Autodesk Fusion 360 part; units mm, degrees
(part 3 of 4)
extrude "GPU lower metal tab exit (1)" cut sketch "草图12 (4)" along normal blind 20.2 bodies 34 in component "18_ONE_PIECE_REAR_LOAD_BEAM_304_45mm"
ref_plane "工作平面13" through (0, -253.84, 0) normal (0, 1, 0) x (0, 0, 1) in component "18_ONE_PIECE_REAR_LOAD_BEAM_304_45mm"
sketch "草图13 (4)" plane through (0, -253.84, 0) normal (0, 1, 0) x (1, 0, 0) in component "18_ONE_PIECE_REAR_LOAD_BEAM_304_45mm"
  circle A0 through (5.7, -132, 507.68) (3.15, -130.5278, 507.68) (3.15, -133.4722, 507.68)
extrude "Rear end screw clearance" cut sketch "草图13 (4)" along normal blind 8 contours A0 in plane through (0, 253.84, 0) normal (0, 1, 0) bodies 34 in component "18_ONE_PIECE_REAR_LOAD_BEAM_304_45mm"
ref_plane "工作平面14" through (0, -256.84, 0) normal (0, 1, 0) x (0, 0, 1) in component "18_ONE_PIECE_REAR_LOAD_BEAM_304_45mm"
sketch "草图14 (4)" plane through (0, -256.84, 0) normal (0, 1, 0) x (1, 0, 0) in component "18_ONE_PIECE_REAR_LOAD_BEAM_304_45mm"
  circle A0 through (7.3, -132, 513.68) (2.35, -129.1421, 513.68) (2.35, -134.8579, 513.68)
extrude "Rear end screw head well leaving 3 mm web" cut sketch "草图14 (4)" along normal blind 5.01 contours A0 in plane through (0, 256.84, 0) normal (0, 1, 0) bodies 34 in component "18_ONE_PIECE_REAR_LOAD_BEAM_304_45mm"
ref_plane "工作平面15" through (0, -253.84, 0) normal (0, 1, 0) x (0, 0, 1) in component "18_ONE_PIECE_REAR_LOAD_BEAM_304_45mm"
sketch "草图15 (3)" plane through (0, -253.84, 0) normal (0, 1, 0) x (1, 0, 0) in component "18_ONE_PIECE_REAR_LOAD_BEAM_304_45mm"
  circle A0 through (295.7, -132, 507.68) (293.15, -130.5278, 507.68) (293.15, -133.4722, 507.68)
extrude "Rear end screw clearance (1)" cut sketch "草图15 (3)" along normal blind 8 contours A0 in plane through (0, 253.84, 0) normal (0, 1, 0) bodies 34 in component "18_ONE_PIECE_REAR_LOAD_BEAM_304_45mm"
ref_plane "工作平面16" through (0, -256.84, 0) normal (0, 1, 0) x (0, 0, 1) in component "18_ONE_PIECE_REAR_LOAD_BEAM_304_45mm"
sketch "草图16 (3)" plane through (0, -256.84, 0) normal (0, 1, 0) x (1, 0, 0) in component "18_ONE_PIECE_REAR_LOAD_BEAM_304_45mm"
  circle A0 through (297.3, -132, 513.68) (292.35, -129.1421, 513.68) (292.35, -134.8579, 513.68)
extrude "Rear end screw head well leaving 3 mm web (1)" cut sketch "草图16 (3)" along normal blind 5.01 contours A0 in plane through (0, 256.84, 0) normal (0, 1, 0) bodies 34 in component "18_ONE_PIECE_REAR_LOAD_BEAM_304_45mm"
ref_plane "工作平面1" through (0, 0, 148) normal (0, 0, 1) x (1, 0, 0) in component "20_ONE_PIECE_DUAL_140_FAN_RAIL_284mm"
sketch "草图1 (31)" plane through (0, 0, 148) normal (0, 0, 1) x (1, 0, 0) in component "20_ONE_PIECE_DUAL_140_FAN_RAIL_284mm"
  line L0 (12.4, -25) -> (296.4, -25)
  line L1 (296.4, -25) -> (296.4, -19)
  line L2 (296.4, -19) -> (12.4, -19)
  line L3 (12.4, -19) -> (12.4, -25)
extrude "One piece dual fan lower mounting rail" add sketch "草图1 (31)" along normal blind 12 separate body makes body 35 in component "20_ONE_PIECE_DUAL_140_FAN_RAIL_284mm"
ref_plane "工作平面2" through (0, 0, 140) normal (0, 0, 1) x (1, 0, 0) in component "20_ONE_PIECE_DUAL_140_FAN_RAIL_284mm"
sketch "草图2 (22)" plane through (0, 0, 140) normal (0, 0, 1) x (1, 0, 0) in component "20_ONE_PIECE_DUAL_140_FAN_RAIL_284mm"
  line L0 (45, -19) -> (55, -19)
  line L1 (55, -19) -> (55, 6)
  line L2 (55, 6) -> (45, 6)
  line L3 (45, 6) -> (45, -19)
extrude "Frame bearing arm" add sketch "草图2 (22)" along normal blind 14 bodies 35 in component "20_ONE_PIECE_DUAL_140_FAN_RAIL_284mm"
ref_plane "工作平面3" through (0, 0, 140) normal (0, 0, 1) x (1, 0, 0) in component "20_ONE_PIECE_DUAL_140_FAN_RAIL_284mm"
sketch "草图3 (21)" plane through (0, 0, 140) normal (0, 0, 1) x (1, 0, 0) in component "20_ONE_PIECE_DUAL_140_FAN_RAIL_284mm"
  circle A0 centre (50, 2) radius 1.7
extrude "Fan arm M3 clearance" cut sketch "草图3 (21)" along normal blind 14 bodies 35 in component "20_ONE_PIECE_DUAL_140_FAN_RAIL_284mm"
ref_plane "工作平面4" through (0, 0, 143) normal (0, 0, 1) x (1, 0, 0) in component "20_ONE_PIECE_DUAL_140_FAN_RAIL_284mm"
sketch "草图4 (21)" plane through (0, 0, 143) normal (0, 0, 1) x (1, 0, 0) in component "20_ONE_PIECE_DUAL_140_FAN_RAIL_284mm"
  circle A0 centre (50, 2) radius 3.3
extrude "Fan arm screw well for M3x6 leaving 3 mm web" cut sketch "草图4 (21)" along normal blind 11.01 bodies 35 in component "20_ONE_PIECE_DUAL_140_FAN_RAIL_284mm"
ref_plane "工作平面5" through (0, 0, 140) normal (0, 0, 1) x (1, 0, 0) in component "20_ONE_PIECE_DUAL_140_FAN_RAIL_284mm"
sketch "草图5 (20)" plane through (0, 0, 140) normal (0, 0, 1) x (1, 0, 0) in component "20_ONE_PIECE_DUAL_140_FAN_RAIL_284mm"
  line L0 (105, -19) -> (115, -19)
  line L1 (115, -19) -> (115, 6)
  line L2 (115, 6) -> (105, 6)
  line L3 (105, 6) -> (105, -19)
extrude "Frame bearing arm (1)" add sketch "草图5 (20)" along normal blind 14 bodies 35 in component "20_ONE_PIECE_DUAL_140_FAN_RAIL_284mm"
ref_plane "工作平面6" through (0, 0, 140) normal (0, 0, 1) x (1, 0, 0) in component "20_ONE_PIECE_DUAL_140_FAN_RAIL_284mm"
sketch "草图6 (18)" plane through (0, 0, 140) normal (0, 0, 1) x (1, 0, 0) in component "20_ONE_PIECE_DUAL_140_FAN_RAIL_284mm"
  circle A0 centre (110, 2) radius 1.7
extrude "Fan arm M3 clearance (1)" cut sketch "草图6 (18)" along normal blind 14 bodies 35 in component "20_ONE_PIECE_DUAL_140_FAN_RAIL_284mm"
ref_plane "工作平面7" through (0, 0, 143) normal (0, 0, 1) x (1, 0, 0) in component "20_ONE_PIECE_DUAL_140_FAN_RAIL_284mm"
sketch "草图7 (15)" plane through (0, 0, 143) normal (0, 0, 1) x (1, 0, 0) in component "20_ONE_PIECE_DUAL_140_FAN_RAIL_284mm"
  circle A0 centre (110, 2) radius 3.3
extrude "Fan arm screw well for M3x6 leaving 3 mm web (1)" cut sketch "草图7 (15)" along normal blind 11.01 bodies 35 in component "20_ONE_PIECE_DUAL_140_FAN_RAIL_284mm"
ref_plane "工作平面8" through (0, 0, 140) normal (0, 0, 1) x (1, 0, 0) in component "20_ONE_PIECE_DUAL_140_FAN_RAIL_284mm"
sketch "草图8 (13)" plane through (0, 0, 140) normal (0, 0, 1) x (1, 0, 0) in component "20_ONE_PIECE_DUAL_140_FAN_RAIL_284mm"
  line L0 (195, -19) -> (205, -19)
  line L1 (205, -19) -> (205, 6)
  line L2 (205, 6) -> (195, 6)
  line L3 (195, 6) -> (195, -19)
extrude "Frame bearing arm (2)" add sketch "草图8 (13)" along normal blind 14 bodies 35 in component "20_ONE_PIECE_DUAL_140_FAN_RAIL_284mm"
ref_plane "工作平面9" through (0, 0, 140) normal (0, 0, 1) x (1, 0, 0) in component "20_ONE_PIECE_DUAL_140_FAN_RAIL_284mm"
sketch "草图9 (10)" plane through (0, 0, 140) normal (0, 0, 1) x (1, 0, 0) in component "20_ONE_PIECE_DUAL_140_FAN_RAIL_284mm"
  circle A0 centre (200, 2) radius 1.7
extrude "Fan arm M3 clearance (2)" cut sketch "草图9 (10)" along normal blind 14 bodies 35 in component "20_ONE_PIECE_DUAL_140_FAN_RAIL_284mm"
ref_plane "工作平面10" through (0, 0, 143) normal (0, 0, 1) x (1, 0, 0) in component "20_ONE_PIECE_DUAL_140_FAN_RAIL_284mm"
sketch "草图10 (6)" plane through (0, 0, 143) normal (0, 0, 1) x (1, 0, 0) in component "20_ONE_PIECE_DUAL_140_FAN_RAIL_284mm"
  circle A0 centre (200, 2) radius 3.3
extrude "Fan arm screw well for M3x6 leaving 3 mm web (2)" cut sketch "草图10 (6)" along normal blind 11.01 bodies 35 in component "20_ONE_PIECE_DUAL_140_FAN_RAIL_284mm"
ref_plane "工作平面11" through (0, 0, 140) normal (0, 0, 1) x (1, 0, 0) in component "20_ONE_PIECE_DUAL_140_FAN_RAIL_284mm"
sketch "草图11 (5)" plane through (0, 0, 140) normal (0, 0, 1) x (1, 0, 0) in component "20_ONE_PIECE_DUAL_140_FAN_RAIL_284mm"
  line L0 (260, -19) -> (270, -19)
  line L1 (270, -19) -> (270, 6)
  line L2 (270, 6) -> (260, 6)
  line L3 (260, 6) -> (260, -19)
extrude "Frame bearing arm (3)" add sketch "草图11 (5)" along normal blind 14 bodies 35 in component "20_ONE_PIECE_DUAL_140_FAN_RAIL_284mm"
ref_plane "工作平面12" through (0, 0, 140) normal (0, 0, 1) x (1, 0, 0) in component "20_ONE_PIECE_DUAL_140_FAN_RAIL_284mm"
sketch "草图12 (5)" plane through (0, 0, 140) normal (0, 0, 1) x (1, 0, 0) in component "20_ONE_PIECE_DUAL_140_FAN_RAIL_284mm"
  circle A0 centre (265, 2) radius 1.7
extrude "Fan arm M3 clearance (3)" cut sketch "草图12 (5)" along normal blind 14 bodies 35 in component "20_ONE_PIECE_DUAL_140_FAN_RAIL_284mm"
ref_plane "工作平面13" through (0, 0, 143) normal (0, 0, 1) x (1, 0, 0) in component "20_ONE_PIECE_DUAL_140_FAN_RAIL_284mm"
sketch "草图13 (5)" plane through (0, 0, 143) normal (0, 0, 1) x (1, 0, 0) in component "20_ONE_PIECE_DUAL_140_FAN_RAIL_284mm"
  circle A0 centre (265, 2) radius 3.3
extrude "Fan arm screw well for M3x6 leaving 3 mm web (3)" cut sketch "草图13 (5)" along normal blind 11.01 bodies 35 in component "20_ONE_PIECE_DUAL_140_FAN_RAIL_284mm"
ref_plane "工作平面10" through (0, 0, 143) normal (0, 0, 1) x (1, 0, 0) in component "19_PCI_LONGITUDINAL_BOARD_RAIL_243_84mm"
sketch "草图10 (7)" plane through (0, 0, 143) normal (0, 0, 1) x (1, 0, 0) in component "19_PCI_LONGITUDINAL_BOARD_RAIL_243_84mm"
  circle A0 centre (4, 20) radius 3.3
extrude "M3x6 rail mounting head well" cut sketch "草图10 (7)" along normal blind 5.01 bodies 31 in component "19_PCI_LONGITUDINAL_BOARD_RAIL_243_84mm"
ref_plane "工作平面11" through (0, 0, 143) normal (0, 0, 1) x (1, 0, 0) in component "19_PCI_LONGITUDINAL_BOARD_RAIL_243_84mm"
sketch "草图11 (6)" plane through (0, 0, 143) normal (0, 0, 1) x (1, 0, 0) in component "19_PCI_LONGITUDINAL_BOARD_RAIL_243_84mm"
  circle A0 centre (4, 225) radius 3.3
extrude "M3x6 rail mounting head well (1)" cut sketch "草图11 (6)" along normal blind 5.01 bodies 31 in component "19_PCI_LONGITUDINAL_BOARD_RAIL_243_84mm"
ref_plane "工作平面10" through (0, 0, 143) normal (0, 0, 1) x (1, 0, 0) in component "19_CPU_LONGITUDINAL_BOARD_RAIL_243_84mm"
sketch "草图10 (8)" plane through (0, 0, 143) normal (0, 0, 1) x (1, 0, 0) in component "19_CPU_LONGITUDINAL_BOARD_RAIL_243_84mm"
  circle A0 centre (294, 20) radius 3.3
extrude "M3x6 rail mounting head well'" cut sketch "草图10 (8)" along normal blind 5.01 bodies 33 in component "19_CPU_LONGITUDINAL_BOARD_RAIL_243_84mm"
ref_plane "工作平面11" through (0, 0, 143) normal (0, 0, 1) x (1, 0, 0) in component "19_CPU_LONGITUDINAL_BOARD_RAIL_243_84mm"
sketch "草图11 (7)" plane through (0, 0, 143) normal (0, 0, 1) x (1, 0, 0) in component "19_CPU_LONGITUDINAL_BOARD_RAIL_243_84mm"
  circle A0 centre (294, 225) radius 3.3
extrude "M3x6 rail mounting head well (1)'" cut sketch "草图11 (7)" along normal blind 5.01 bodies 33 in component "19_CPU_LONGITUDINAL_BOARD_RAIL_243_84mm"
ref_plane "工作平面15" through (0, 0, 143) normal (0, 0, 1) x (1, 0, 0) in component "19_MID_LONGITUDINAL_BOARD_RAIL_243_84mm"
sketch "草图15 (4)" plane through (0, 0, 143) normal (0, 0, 1) x (1, 0, 0) in component "19_MID_LONGITUDINAL_BOARD_RAIL_243_84mm"
  circle A0 centre (134, 3) radius 3.3
extrude "M3x6 rail mounting head well''" cut sketch "草图15 (4)" along normal blind 5.01 bodies 32 in component "19_MID_LONGITUDINAL_BOARD_RAIL_243_84mm"
ref_plane "工作平面16" through (0, 0, 143) normal (0, 0, 1) x (1, 0, 0) in component "19_MID_LONGITUDINAL_BOARD_RAIL_243_84mm"
sketch "草图16 (4)" plane through (0, 0, 143) normal (0, 0, 1) x (1, 0, 0) in component "19_MID_LONGITUDINAL_BOARD_RAIL_243_84mm"
  circle A0 centre (134, 222.5) radius 3.3
extrude "M3x6 rail mounting head well (1)''" cut sketch "草图16 (4)" along normal blind 5.01 bodies 32 in component "19_MID_LONGITUDINAL_BOARD_RAIL_243_84mm"
ref_plane "工作平面23" through (0, 0, 143) normal (0, 0, 1) x (1, 0, 0) in component "07_GPU_REINFORCED_REAR_TOWER"
sketch "草图23" plane through (0, 0, 143) normal (0, 0, 1) x (1, 0, 0) in component "07_GPU_REINFORCED_REAR_TOWER"
  circle A0 centre (80, 248.5) radius 3.3
extrude "M3x6 tower base screw head well" cut sketch "草图23" along normal blind 5.01 bodies 26 in component "07_GPU_REINFORCED_REAR_TOWER"
ref_plane "工作平面24" through (0, 0, 143) normal (0, 0, 1) x (1, 0, 0) in component "07_GPU_REINFORCED_REAR_TOWER"
sketch "草图24" plane through (0, 0, 143) normal (0, 0, 1) x (1, 0, 0) in component "07_GPU_REINFORCED_REAR_TOWER"
  circle A0 centre (140, 248.5) radius 3.3
extrude "M3x6 tower base screw head well (1)" cut sketch "草图24" along normal blind 5.01 bodies 26 in component "07_GPU_REINFORCED_REAR_TOWER"
ref_plane "工作平面25" through (0, 0, 143) normal (0, 0, 1) x (1, 0, 0) in component "07_GPU_REINFORCED_REAR_TOWER"
sketch "草图25" plane through (0, 0, 143) normal (0, 0, 1) x (1, 0, 0) in component "07_GPU_REINFORCED_REAR_TOWER"
  circle A0 centre (158, 248.5) radius 3.3
extrude "M3x6 tower base screw head well (2)" cut sketch "草图25" along normal blind 5.01 bodies 26 in component "07_GPU_REINFORCED_REAR_TOWER"
ref_plane "工作平面26" through (0, -263, 0) normal (0, 1, 0) x (0, 0, 1) in component "07_GPU_REINFORCED_REAR_TOWER"
sketch "草图26" plane through (0, -263, 0) normal (0, 1, 0) x (1, 0, 0) in component "07_GPU_REINFORCED_REAR_TOWER"
  circle A0 through (83.3, -262, 526) (78.35, -259.1421, 526) (78.35, -264.8579, 526)
extrude "Upper sliding screw head channel end A" cut sketch "草图26" along normal blind 7.01 contours A0 in plane through (0, 263, 0) normal (0, 1, 0) bodies 26 in component "07_GPU_REINFORCED_REAR_TOWER"
ref_plane "工作平面27" through (0, -263, 0) normal (0, 1, 0) x (0, 0, 1) in component "07_GPU_REINFORCED_REAR_TOWER"
sketch "草图27" plane through (0, -263, 0) normal (0, 1, 0) x (1, 0, 0) in component "07_GPU_REINFORCED_REAR_TOWER"
  circle A0 through (83.3, -292, 526) (78.35, -289.1421, 526) (78.35, -294.8579, 526)
extrude "Upper sliding screw head channel end B" cut sketch "草图27" along normal blind 7.01 contours A0 in plane through (0, 263, 0) normal (0, 1, 0) bodies 26 in component "07_GPU_REINFORCED_REAR_TOWER"
ref_plane "工作平面28" through (0, 0, 262) normal (0, 0, 1) x (1, 0, 0) in component "07_GPU_REINFORCED_REAR_TOWER"
sketch "草图28" plane through (0, 0, 262) normal (0, 0, 1) x (1, 0, 0) in component "07_GPU_REINFORCED_REAR_TOWER"
  line L0 (76.7, 263) -> (83.3, 263)
  line L1 (83.3, 263) -> (83.3, 270.01)
  line L2 (83.3, 270.01) -> (76.7, 270.01)
  line L3 (76.7, 270.01) -> (76.7, 263)
extrude "Upper sliding screw head channel middle" cut sketch "草图28" along normal blind 30 bodies 26 in component "07_GPU_REINFORCED_REAR_TOWER"
ref_plane "工作平面29" through (0, -263, 0) normal (0, 1, 0) x (0, 0, 1) in component "07_GPU_REINFORCED_REAR_TOWER"
sketch "草图29" plane through (0, -263, 0) normal (0, 1, 0) x (1, 0, 0) in component "07_GPU_REINFORCED_REAR_TOWER"
  circle A0 through (83.3, -157, 526) (78.35, -154.1421, 526) (78.35, -159.8579, 526)
extrude "Lower sliding screw head channel end A" cut sketch "草图29" along normal blind 7.01 contours A0 in plane through (0, 263, 0) normal (0, 1, 0) bodies 26 in component "07_GPU_REINFORCED_REAR_TOWER"
ref_plane "工作平面30" through (0, -263, 0) normal (0, 1, 0) x (0, 0, 1) in component "07_GPU_REINFORCED_REAR_TOWER"
sketch "草图30" plane through (0, -263, 0) normal (0, 1, 0) x (1, 0, 0) in component "07_GPU_REINFORCED_REAR_TOWER"
  circle A0 through (83.3, -165, 526) (78.35, -162.1421, 526) (78.35, -167.8579, 526)
extrude "Lower sliding screw head channel end B" cut sketch "草图30" along normal blind 7.01 contours A0 in plane through (0, 263, 0) normal (0, 1, 0) bodies 26 in component "07_GPU_REINFORCED_REAR_TOWER"
ref_plane "工作平面31" through (0, 0, 157) normal (0, 0, 1) x (1, 0, 0) in component "07_GPU_REINFORCED_REAR_TOWER"
sketch "草图31" plane through (0, 0, 157) normal (0, 0, 1) x (1, 0, 0) in component "07_GPU_REINFORCED_REAR_TOWER"
  line L0 (76.7, 263) -> (83.3, 263)
  line L1 (83.3, 263) -> (83.3, 270.01)
  line L2 (83.3, 270.01) -> (76.7, 270.01)
  line L3 (76.7, 270.01) -> (76.7, 263)
extrude "Lower sliding screw head channel middle" cut sketch "草图31" along normal blind 8 bodies 26 in component "07_GPU_REINFORCED_REAR_TOWER"
ref_plane "工作平面32" through (0, -263, 0) normal (0, 1, 0) x (0, 0, 1) in component "07_GPU_REINFORCED_REAR_TOWER"
sketch "草图32" plane through (0, -263, 0) normal (0, 1, 0) x (1, 0, 0) in component "07_GPU_REINFORCED_REAR_TOWER"
  circle A0 through (167.3, -262, 526) (162.35, -259.1421, 526) (162.35, -264.8579, 526)
extrude "Upper sliding screw head channel end A (1)" cut sketch "草图32" along normal blind 7.01 contours A0 in plane through (0, 263, 0) normal (0, 1, 0) bodies 26 in component "07_GPU_REINFORCED_REAR_TOWER"
ref_plane "工作平面33" through (0, -263, 0) normal (0, 1, 0) x (0, 0, 1) in component "07_GPU_REINFORCED_REAR_TOWER"
sketch "草图33" plane through (0, -263, 0) normal (0, 1, 0) x (1, 0, 0) in component "07_GPU_REINFORCED_REAR_TOWER"
  circle A0 through (167.3, -292, 526) (162.35, -289.1421, 526) (162.35, -294.8579, 526)
extrude "Upper sliding screw head channel end B (1)" cut sketch "草图33" along normal blind 7.01 contours A0 in plane through (0, 263, 0) normal (0, 1, 0) bodies 26 in component "07_GPU_REINFORCED_REAR_TOWER"
ref_plane "工作平面34" through (0, 0, 262) normal (0, 0, 1) x (1, 0, 0) in component "07_GPU_REINFORCED_REAR_TOWER"
sketch "草图34" plane through (0, 0, 262) normal (0, 0, 1) x (1, 0, 0) in component "07_GPU_REINFORCED_REAR_TOWER"
  line L0 (160.7, 263) -> (167.3, 263)
  line L1 (167.3, 263) -> (167.3, 270.01)
  line L2 (167.3, 270.01) -> (160.7, 270.01)
  line L3 (160.7, 270.01) -> (160.7, 263)
extrude "Upper sliding screw head channel middle (1)" cut sketch "草图34" along normal blind 30 bodies 26 in component "07_GPU_REINFORCED_REAR_TOWER"
ref_plane "工作平面35" through (0, -263, 0) normal (0, 1, 0) x (0, 0, 1) in component "07_GPU_REINFORCED_REAR_TOWER"
sketch "草图35" plane through (0, -263, 0) normal (0, 1, 0) x (1, 0, 0) in component "07_GPU_REINFORCED_REAR_TOWER"
  circle A0 through (167.3, -157, 526) (162.35, -154.1421, 526) (162.35, -159.8579, 526)
extrude "Lower sliding screw head channel end A (1)" cut sketch "草图35" along normal blind 7.01 contours A0 in plane through (0, 263, 0) normal (0, 1, 0) bodies 26 in component "07_GPU_REINFORCED_REAR_TOWER"
ref_plane "工作平面36" through (0, -263, 0) normal (0, 1, 0) x (0, 0, 1) in component "07_GPU_REINFORCED_REAR_TOWER"
sketch "草图36" plane through (0, -263, 0) normal (0, 1, 0) x (1, 0, 0) in component "07_GPU_REINFORCED_REAR_TOWER"
  circle A0 through (167.3, -165, 526) (162.35, -162.1421, 526) (162.35, -167.8579, 526)
extrude "Lower sliding screw head channel end B (1)" cut sketch "草图36" along normal blind 7.01 contours A0 in plane through (0, 263, 0) normal (0, 1, 0) bodies 26 in component "07_GPU_REINFORCED_REAR_TOWER"
ref_plane "工作平面37" through (0, 0, 157) normal (0, 0, 1) x (1, 0, 0) in component "07_GPU_REINFORCED_REAR_TOWER"
sketch "草图37" plane through (0, 0, 157) normal (0, 0, 1) x (1, 0, 0) in component "07_GPU_REINFORCED_REAR_TOWER"
  line L0 (160.7, 263) -> (167.3, 263)
  line L1 (167.3, 263) -> (167.3, 270.01)
  line L2 (167.3, 270.01) -> (160.7, 270.01)
  line L3 (160.7, 270.01) -> (160.7, 263)
extrude "Lower sliding screw head channel middle (1)" cut sketch "草图37" along normal blind 8 bodies 26 in component "07_GPU_REINFORCED_REAR_TOWER"
ref_plane "工作平面9" through (0, -255.1, 0) normal (0, 1, 0) x (0, 0, 1) in component "08_GPU_UPPER_EAR_LEDGE_ADJUSTABLE"
sketch "草图9 (11)" plane through (0, -255.1, 0) normal (0, 1, 0) x (1, 0, 0) in component "08_GPU_UPPER_EAR_LEDGE_ADJUSTABLE"
  circle A0 through (82.35, -276, 510.2) (78.825, -273.9648, 510.2) (78.825, -278.0352, 510.2)
extrude "Rear entry H4.5 insert for sliding M3x6 clamp" cut sketch "草图9 (11)" along normal blind 4.91 contours A0 in plane through (0, 255.1, 0) normal (0, 1, 0) bodies 27 in component "08_GPU_UPPER_EAR_LEDGE_ADJUSTABLE"
ref_plane "工作平面10" through (0, -255.1, 0) normal (0, 1, 0) x (0, 0, 1) in component "08_GPU_UPPER_EAR_LEDGE_ADJUSTABLE"
sketch "草图10 (9)" plane through (0, -255.1, 0) normal (0, 1, 0) x (1, 0, 0) in component "08_GPU_UPPER_EAR_LEDGE_ADJUSTABLE"
  circle A0 through (166.35, -276, 510.2) (162.825, -273.9648, 510.2) (162.825, -278.0352, 510.2)
extrude "Rear entry H4.5 insert for sliding M3x6 clamp (1)" cut sketch "草图10 (9)" along normal blind 4.91 contours A0 in plane through (0, 255.1, 0) normal (0, 1, 0) bodies 27 in component "08_GPU_UPPER_EAR_LEDGE_ADJUSTABLE"
ref_plane "工作平面8" through (0, -255.1, 0) normal (0, 1, 0) x (0, 0, 1) in component "08_GPU_LOWER_TWO_TAB_RECEIVER_ADJUSTABLE"
sketch "草图8 (14)" plane through (0, -255.1, 0) normal (0, 1, 0) x (1, 0, 0) in component "08_GPU_LOWER_TWO_TAB_RECEIVER_ADJUSTABLE"
  circle A0 through (82.35, -157, 510.2) (78.825, -154.9648, 510.2) (78.825, -159.0352, 510.2)
extrude "Rear entry H4.5 insert for sliding M3x6 clamp'" cut sketch "草图8 (14)" along normal blind 4.91 contours A0 in plane through (0, 255.1, 0) normal (0, 1, 0) bodies 28 in component "08_GPU_LOWER_TWO_TAB_RECEIVER_ADJUSTABLE"
ref_plane "工作平面9" through (0, -255.1, 0) normal (0, 1, 0) x (0, 0, 1) in component "08_GPU_LOWER_TWO_TAB_RECEIVER_ADJUSTABLE"
sketch "草图9 (12)" plane through (0, -255.1, 0) normal (0, 1, 0) x (1, 0, 0) in component "08_GPU_LOWER_TWO_TAB_RECEIVER_ADJUSTABLE"
  circle A0 through (166.35, -157, 510.2) (162.825, -154.9648, 510.2) (162.825, -159.0352, 510.2)
extrude "Rear entry H4.5 insert for sliding M3x6 clamp (1)'" cut sketch "草图9 (12)" along normal blind 4.91 contours A0 in plane through (0, 255.1, 0) normal (0, 1, 0) bodies 28 in component "08_GPU_LOWER_TWO_TAB_RECEIVER_ADJUSTABLE"
ref_plane "工作平面9" through (0, 10, 0) normal (0, 1, 0) x (0, 0, 1) in component "12_front_PCI_SUPPORT_FRAME"
sketch "草图9 (13)" plane through (0, 10, 0) normal (0, 1, 0) x (1, 0, 0) in component "12_front_PCI_SUPPORT_FRAME"
  circle A0 through (21.21, -8, -20) (18.66, -6.5278, -20) (18.66, -9.4722, -20)
extrude "Front corner M3 clearance" cut sketch "草图9 (13)" along normal blind 16.01 contours A0 in plane through (0, -10, 0) normal (0, 1, 0) bodies 24 in component "12_front_PCI_SUPPORT_FRAME"
ref_plane "工作平面10" through (0, 10, 0) normal (0, 1, 0) x (0, 0, 1) in component "12_front_PCI_SUPPORT_FRAME"
sketch "草图10 (10)" plane through (0, 10, 0) normal (0, 1, 0) x (1, 0, 0) in component "12_front_PCI_SUPPORT_FRAME"
  circle A0 through (22.81, -8, -20) (17.86, -5.1421, -20) (17.86, -10.8579, -20)
extrude "Front corner screw well leaving 3 mm web" cut sketch "草图10 (10)" along normal blind 13 contours A0 in plane through (0, -10, 0) normal (0, 1, 0) bodies 24 in component "12_front_PCI_SUPPORT_FRAME"
ref_plane "工作平面9" through (0, -6, 0) normal (0, 1, 0) x (0, 0, 1) in component "16_PCI_INSET_SIDE_16_45mm"
sketch "草图9 (14)" plane through (0, -6, 0) normal (0, 1, 0) x (1, 0, 0) in component "16_PCI_INSET_SIDE_16_45mm"
  circle A0 through (21.86, -8, 12) (18.335, -5.9648, 12) (18.335, -10.0352, 12)
extrude "Front corner H4.5 insert" cut sketch "草图9 (14)" along normal blind 6.5 contours A0 in plane through (0, 6, 0) normal (0, 1, 0) bodies 30 in component "16_PCI_INSET_SIDE_16_45mm"
ref_plane "工作平面11" through (0, 10, 0) normal (0, 1, 0) x (0, 0, 1) in component "12_front_PCI_SUPPORT_FRAME"
sketch "草图11 (8)" plane through (0, 10, 0) normal (0, 1, 0) x (1, 0, 0) in component "12_front_PCI_SUPPORT_FRAME"
  circle A0 through (6.64, -132, -20) (4.09, -130.5278, -20) (4.09, -133.4722, -20)
extrude "Front corner M3 clearance (1)" cut sketch "草图11 (8)" along normal blind 16.01 contours A0 in plane through (0, -10, 0) normal (0, 1, 0) bodies 24 in component "12_front_PCI_SUPPORT_FRAME"
ref_plane "工作平面12" through (0, 10, 0) normal (0, 1, 0) x (0, 0, 1) in component "12_front_PCI_SUPPORT_FRAME"
sketch "草图12 (6)" plane through (0, 10, 0) normal (0, 1, 0) x (1, 0, 0) in component "12_front_PCI_SUPPORT_FRAME"
  circle A0 through (8.24, -132, -20) (3.29, -129.1421, -20) (3.29, -134.8579, -20)
extrude "Front corner screw well leaving 3 mm web (1)" cut sketch "草图12 (6)" along normal blind 13 contours A0 in plane through (0, -10, 0) normal (0, 1, 0) bodies 24 in component "12_front_PCI_SUPPORT_FRAME"
ref_plane "工作平面10" through (0, -6, 0) normal (0, 1, 0) x (0, 0, 1) in component "16_PCI_INSET_SIDE_16_45mm"
sketch "草图10 (11)" plane through (0, -6, 0) normal (0, 1, 0) x (1, 0, 0) in component "16_PCI_INSET_SIDE_16_45mm"
  circle A0 through (7.29, -132, 12) (3.765, -129.9648, 12) (3.765, -134.0352, 12)
extrude "Front corner H4.5 insert (1)" cut sketch "草图10 (11)" along normal blind 6.5 contours A0 in plane through (0, 6, 0) normal (0, 1, 0) bodies 30 in component "16_PCI_INSET_SIDE_16_45mm"
ref_plane "工作平面8" through (0, 10, 0) normal (0, 1, 0) x (0, 0, 1) in component "12_front_CPU_SUPPORT_FRAME"
sketch "草图8 (15)" plane through (0, 10, 0) normal (0, 1, 0) x (1, 0, 0) in component "12_front_CPU_SUPPORT_FRAME"
  circle A0 through (296.15, -8, -20) (293.6, -6.5278, -20) (293.6, -9.4722, -20)
extrude "Front corner M3 clearance'" cut sketch "草图8 (15)" along normal blind 16.01 contours A0 in plane through (0, -10, 0) normal (0, 1, 0) bodies 25 in component "12_front_CPU_SUPPORT_FRAME"
ref_plane "工作平面9" through (0, 10, 0) normal (0, 1, 0) x (0, 0, 1) in component "12_front_CPU_SUPPORT_FRAME"
sketch "草图9 (15)" plane through (0, 10, 0) normal (0, 1, 0) x (1, 0, 0) in component "12_front_CPU_SUPPORT_FRAME"
  circle A0 through (297.75, -8, -20) (292.8, -5.1421, -20) (292.8, -10.8579, -20)
extrude "Front corner screw well leaving 3 mm web'" cut sketch "草图9 (15)" along normal blind 13 contours A0 in plane through (0, -10, 0) normal (0, 1, 0) bodies 25 in component "12_front_CPU_SUPPORT_FRAME"
ref_plane "工作平面7" through (0, -6, 0) normal (0, 1, 0) x (0, 0, 1) in component "16_CPU_VERTICAL_SIDE_FLUSH_TO_BEAM"
sketch "草图7 (16)" plane through (0, -6, 0) normal (0, 1, 0) x (1, 0, 0) in component "16_CPU_VERTICAL_SIDE_FLUSH_TO_BEAM"
  circle A0 through (296.8, -8, 12) (293.275, -5.9648, 12) (293.275, -10.0352, 12)
extrude "Front corner H4.5 insert'" cut sketch "草图7 (16)" along normal blind 6.5 contours A0 in plane through (0, 6, 0) normal (0, 1, 0) bodies 29 in component "16_CPU_VERTICAL_SIDE_FLUSH_TO_BEAM"
ref_plane "工作平面10" through (0, 10, 0) normal (0, 1, 0) x (0, 0, 1) in component "12_front_CPU_SUPPORT_FRAME"
sketch "草图10 (12)" plane through (0, 10, 0) normal (0, 1, 0) x (1, 0, 0) in component "12_front_CPU_SUPPORT_FRAME"
  circle A0 through (296.15, -132, -20) (293.6, -130.5278, -20) (293.6, -133.4722, -20)
extrude "Front corner M3 clearance (1)'" cut sketch "草图10 (12)" along normal blind 16.01 contours A0 in plane through (0, -10, 0) normal (0, 1, 0) bodies 25 in component "12_front_CPU_SUPPORT_FRAME"
ref_plane "工作平面11" through (0, 10, 0) normal (0, 1, 0) x (0, 0, 1) in component "12_front_CPU_SUPPORT_FRAME"
sketch "草图11 (9)" plane through (0, 10, 0) normal (0, 1, 0) x (1, 0, 0) in component "12_front_CPU_SUPPORT_FRAME"
  circle A0 through (297.75, -132, -20) (292.8, -129.1421, -20) (292.8, -134.8579, -20)
extrude "Front corner screw well leaving 3 mm web (1)'" cut sketch "草图11 (9)" along normal blind 13 contours A0 in plane through (0, -10, 0) normal (0, 1, 0) bodies 25 in component "12_front_CPU_SUPPORT_FRAME"
ref_plane "工作平面8" through (0, -6, 0) normal (0, 1, 0) x (0, 0, 1) in component "16_CPU_VERTICAL_SIDE_FLUSH_TO_BEAM"
sketch "草图8 (16)" plane through (0, -6, 0) normal (0, 1, 0) x (1, 0, 0) in component "16_CPU_VERTICAL_SIDE_FLUSH_TO_BEAM"
  circle A0 through (296.8, -132, 12) (293.275, -129.9648, 12) (293.275, -134.0352, 12)
extrude "Front corner H4.5 insert (1)'" cut sketch "草图8 (16)" along normal blind 6.5 contours A0 in plane through (0, 6, 0) normal (0, 1, 0) bodies 29 in component "16_CPU_VERTICAL_SIDE_FLUSH_TO_BEAM"
ref_plane "工作平面12" through (0, 0, 0) normal (0, 0, 1) x (1, 0, 0) in component "12_front_CPU_SUPPORT_FRAME"
sketch "草图12 (7)" plane through (0, 0, 0) normal (0, 0, 1) x (1, 0, 0) in component "12_front_CPU_SUPPORT_FRAME"
  line L0 (140, -13) -> (165, -13)
  line L1 (165, -13) -> (165, -10)
  line L2 (165, -10) -> (140, -10)
  line L3 (140, -10) -> (140, -13)
extrude "Integral front seam bridge" add sketch "草图12 (7)" along normal blind 16 bodies 25 in component "12_front_CPU_SUPPORT_FRAME"
ref_plane "工作平面13" through (0, 13, 0) normal (0, 1, 0) x (0, 0, 1) in component "12_front_CPU_SUPPORT_FRAME"
sketch "草图13 (6)" plane through (0, 13, 0) normal (0, 1, 0) x (1, 0, 0) in component "12_front_CPU_SUPPORT_FRAME"
  circle A0 through (147.7, -8, -26) (145.15, -6.5278, -26) (145.15, -9.4722, -26)
extrude "Front seam M3x6 clearance" cut sketch "草图13 (6)" along normal blind 3.01 contours A0 in plane through (0, -13, 0) normal (0, 1, 0) bodies 25 in component "12_front_CPU_SUPPORT_FRAME"
ref_plane "工作平面13" through (0, 10, 0) normal (0, 1, 0) x (0, 0, 1) in component "12_front_PCI_SUPPORT_FRAME"
sketch "草图13 (7)" plane through (0, 10, 0) normal (0, 1, 0) x (1, 0, 0) in component "12_front_PCI_SUPPORT_FRAME"
  circle A0 through (148.35, -8, -20) (144.825, -5.9648, -20) (144.825, -10.0352, -20)
extrude "Front seam H4.5 insert" cut sketch "草图13 (7)" along normal blind 6.5 contours A0 in plane through (0, -10, 0) normal (0, 1, 0) bodies 24 in component "12_front_PCI_SUPPORT_FRAME"
ref_plane "工作平面14" through (0, 0, 124) normal (0, 0, 1) x (1, 0, 0) in component "12_front_CPU_SUPPORT_FRAME"
sketch "草图14 (5)" plane through (0, 0, 124) normal (0, 0, 1) x (1, 0, 0) in component "12_front_CPU_SUPPORT_FRAME"
  line L0 (140, -13) -> (165, -13)
  line L1 (165, -13) -> (165, -10)
  line L2 (165, -10) -> (140, -10)
  line L3 (140, -10) -> (140, -13)
extrude "Integral front seam bridge (1)" add sketch "草图14 (5)" along normal blind 16 bodies 25 in component "12_front_CPU_SUPPORT_FRAME"
ref_plane "工作平面15" through (0, 13, 0) normal (0, 1, 0) x (0, 0, 1) in component "12_front_CPU_SUPPORT_FRAME"
sketch "草图15 (5)" plane through (0, 13, 0) normal (0, 1, 0) x (1, 0, 0) in component "12_front_CPU_SUPPORT_FRAME"
  circle A0 through (147.7, -132, -26) (145.15, -130.5278, -26) (145.15, -133.4722, -26)
extrude "Front seam M3x6 clearance (1)" cut sketch "草图15 (5)" along normal blind 3.01 contours A0 in plane through (0, -13, 0) normal (0, 1, 0) bodies 25 in component "12_front_CPU_SUPPORT_FRAME"
ref_plane "工作平面14" through (0, 10, 0) normal (0, 1, 0) x (0, 0, 1) in component "12_front_PCI_SUPPORT_FRAME"
sketch "草图14 (6)" plane through (0, 10, 0) normal (0, 1, 0) x (1, 0, 0) in component "12_front_PCI_SUPPORT_FRAME"
  circle A0 through (148.35, -132, -20) (144.825, -129.9648, -20) (144.825, -134.0352, -20)
extrude "Front seam H4.5 insert (1)" cut sketch "草图14 (6)" along normal blind 6.5 contours A0 in plane through (0, -10, 0) normal (0, 1, 0) bodies 24 in component "12_front_PCI_SUPPORT_FRAME"
ref_plane "工作平面6" through (0, 0, 0) normal (0, 0, 1) x (1, 0, 0) in component "04_front_GROUND_BAR_290mm_FLAT_PSU"
sketch "草图6 (19)" plane through (0, 0, 0) normal (0, 0, 1) x (1, 0, 0) in component "04_front_GROUND_BAR_290mm_FLAT_PSU"
  line L0 (20.45, 29.92) -> (28.45, 29.92)
  line L1 (28.45, 29.92) -> (28.45, 49.92)
  line L2 (28.45, 49.92) -> (20.45, 49.92)
  line L3 (20.45, 49.92) -> (20.45, 29.92)
extrude "PCI bottom lap end seat" add sketch "草图6 (19)" along normal blind 3.2 bodies 18 in component "04_front_GROUND_BAR_290mm_FLAT_PSU"
ref_plane "工作平面7" through (0, 0, 0) normal (0, 0, 1) x (1, 0, 0) in component "04_front_GROUND_BAR_290mm_FLAT_PSU"
sketch "草图7 (17)" plane through (0, 0, 0) normal (0, 0, 1) x (1, 0, 0) in component "04_front_GROUND_BAR_290mm_FLAT_PSU"
  line L0 (286.45, 29.92) -> (294.45, 29.92)
  line L1 (294.45, 29.92) -> (294.45, 49.92)
  line L2 (294.45, 49.92) -> (286.45, 49.92)
  line L3 (286.45, 49.92) -> (286.45, 29.92)
extrude "CPU bottom lap end seat" add sketch "草图7 (17)" along normal blind 3.2 bodies 18 in component "04_front_GROUND_BAR_290mm_FLAT_PSU"
ref_plane "工作平面11" through (0, 0, -0.01) normal (0, 0, 1) x (1, 0, 0) in component "16_PCI_INSET_SIDE_16_45mm"
sketch "草图11 (10)" plane through (0, 0, -0.01) normal (0, 0, 1) x (1, 0, 0) in component "16_PCI_INSET_SIDE_16_45mm"
  line L0 (20.3, 29.77) -> (28.6, 29.77)
  line L1 (28.6, 29.77) -> (28.6, 50.07)
  line L2 (28.6, 50.07) -> (20.3, 50.07)
  line L3 (20.3, 50.07) -> (20.3, 29.77)
extrude "Ground bar seat with lateral print clearance" cut sketch "草图11 (10)" along normal blind 3.21 bodies 30 in component "16_PCI_INSET_SIDE_16_45mm"
ref_plane "工作平面8" through (0, 0, 0) normal (0, 0, 1) x (1, 0, 0) in component "04_front_GROUND_BAR_290mm_FLAT_PSU"
sketch "草图8 (17)" plane through (0, 0, 0) normal (0, 0, 1) x (1, 0, 0) in component "04_front_GROUND_BAR_290mm_FLAT_PSU"
  circle A0 centre (24.45, 39.92) radius 1.7
extrude "Bottom lap M3x6 clearance" cut sketch "草图8 (17)" along normal blind 3.21 bodies 18 in component "04_front_GROUND_BAR_290mm_FLAT_PSU"
ref_plane "工作平面12" through (0, 0, 3.2) normal (0, 0, 1) x (1, 0, 0) in component "16_PCI_INSET_SIDE_16_45mm"
sketch "草图12 (8)" plane through (0, 0, 3.2) normal (0, 0, 1) x (1, 0, 0) in component "16_PCI_INSET_SIDE_16_45mm"
  circle A0 centre (24.45, 39.92) radius 2.35
extrude "Bottom entry H4.5 insert for floor tie" cut sketch "草图12 (8)" along normal blind 6.5 bodies 30 in component "16_PCI_INSET_SIDE_16_45mm"
ref_plane "工作平面9" through (0, 0, -0.01) normal (0, 0, 1) x (1, 0, 0) in component "16_CPU_VERTICAL_SIDE_FLUSH_TO_BEAM"
sketch "草图9 (16)" plane through (0, 0, -0.01) normal (0, 0, 1) x (1, 0, 0) in component "16_CPU_VERTICAL_SIDE_FLUSH_TO_BEAM"
  line L0 (286.3, 29.77) -> (294.6, 29.77)
  line L1 (294.6, 29.77) -> (294.6, 50.07)
  line L2 (294.6, 50.07) -> (286.3, 50.07)
  line L3 (286.3, 50.07) -> (286.3, 29.77)
extrude "Ground bar seat with lateral print clearance'" cut sketch "草图9 (16)" along normal blind 3.21 bodies 29 in component "16_CPU_VERTICAL_SIDE_FLUSH_TO_BEAM"
ref_plane "工作平面9" through (0, 0, 0) normal (0, 0, 1) x (1, 0, 0) in component "04_front_GROUND_BAR_290mm_FLAT_PSU"
sketch "草图9 (17)" plane through (0, 0, 0) normal (0, 0, 1) x (1, 0, 0) in component "04_front_GROUND_BAR_290mm_FLAT_PSU"
  circle A0 centre (290.45, 39.92) radius 1.7
extrude "Bottom lap M3x6 clearance (1)" cut sketch "草图9 (17)" along normal blind 3.21 bodies 18 in component "04_front_GROUND_BAR_290mm_FLAT_PSU"
ref_plane "工作平面10" through (0, 0, 3.2) normal (0, 0, 1) x (1, 0, 0) in component "16_CPU_VERTICAL_SIDE_FLUSH_TO_BEAM"
sketch "草图10 (13)" plane through (0, 0, 3.2) normal (0, 0, 1) x (1, 0, 0) in component "16_CPU_VERTICAL_SIDE_FLUSH_TO_BEAM"
  circle A0 centre (290.45, 39.92) radius 2.35
extrude "Bottom entry H4.5 insert for floor tie'" cut sketch "草图10 (13)" along normal blind 6.5 bodies 29 in component "16_CPU_VERTICAL_SIDE_FLUSH_TO_BEAM"
ref_plane "工作平面17" through (0, 0, 8) normal (0, 0, 1) x (1, 0, 0) in component "05_CENTERED_FLAT_PSU_CRADLE_OPEN_INTAKE"
sketch "草图17 (2)" plane through (0, 0, 8) normal (0, 0, 1) x (1, 0, 0) in component "05_CENTERED_FLAT_PSU_CRADLE_OPEN_INTAKE"
  circle A0 centre (79.4, 39.92) radius 1.7
extrude "Cradle to crossbar screw clearance" cut sketch "草图17 (2)" along normal blind 22.01 bodies 20 in component "05_CENTERED_FLAT_PSU_CRADLE_OPEN_INTAKE"
ref_plane "工作平面18" through (0, 0, 11) normal (0, 0, 1) x (1, 0, 0) in component "05_CENTERED_FLAT_PSU_CRADLE_OPEN_INTAKE"
sketch "草图18 (2)" plane through (0, 0, 11) normal (0, 0, 1) x (1, 0, 0) in component "05_CENTERED_FLAT_PSU_CRADLE_OPEN_INTAKE"
  circle A0 centre (79.4, 39.92) radius 3.3
extrude "Cradle screw well leaving 3 mm web" cut sketch "草图18 (2)" along normal blind 19.01 bodies 20 in component "05_CENTERED_FLAT_PSU_CRADLE_OPEN_INTAKE"
ref_plane "工作平面10" through (0, 0, 1.5) normal (0, 0, 1) x (1, 0, 0) in component "04_front_GROUND_BAR_290mm_FLAT_PSU"
sketch "草图10 (14)" plane through (0, 0, 1.5) normal (0, 0, 1) x (1, 0, 0) in component "04_front_GROUND_BAR_290mm_FLAT_PSU"
  circle A0 centre (79.4, 39.92) radius 2.35
extrude "Top entry H4.5 insert for cradle foot" cut sketch "草图10 (14)" along normal blind 6.51 bodies 18 in component "04_front_GROUND_BAR_290mm_FLAT_PSU"
ref_plane "工作平面19" through (0, 0, 8) normal (0, 0, 1) x (1, 0, 0) in component "05_CENTERED_FLAT_PSU_CRADLE_OPEN_INTAKE"
sketch "草图19 (2)" plane through (0, 0, 8) normal (0, 0, 1) x (1, 0, 0) in component "05_CENTERED_FLAT_PSU_CRADLE_OPEN_INTAKE"
  circle A0 centre (225.4, 39.92) radius 1.7
extrude "Cradle to crossbar screw clearance (1)" cut sketch "草图19 (2)" along normal blind 22.01 bodies 20 in component "05_CENTERED_FLAT_PSU_CRADLE_OPEN_INTAKE"
ref_plane "工作平面20" through (0, 0, 11) normal (0, 0, 1) x (1, 0, 0) in component "05_CENTERED_FLAT_PSU_CRADLE_OPEN_INTAKE"
sketch "草图20 (2)" plane through (0, 0, 11) normal (0, 0, 1) x (1, 0, 0) in component "05_CENTERED_FLAT_PSU_CRADLE_OPEN_INTAKE"
  circle A0 centre (225.4, 39.92) radius 3.3
extrude "Cradle screw well leaving 3 mm web (1)" cut sketch "草图20 (2)" along normal blind 19.01 bodies 20 in component "05_CENTERED_FLAT_PSU_CRADLE_OPEN_INTAKE"
ref_plane "工作平面11" through (0, 0, 1.5) normal (0, 0, 1) x (1, 0, 0) in component "04_front_GROUND_BAR_290mm_FLAT_PSU"
sketch "草图11 (11)" plane through (0, 0, 1.5) normal (0, 0, 1) x (1, 0, 0) in component "04_front_GROUND_BAR_290mm_FLAT_PSU"
  circle A0 centre (225.4, 39.92) radius 2.35
extrude "Top entry H4.5 insert for cradle foot (1)" cut sketch "草图11 (11)" along normal blind 6.51 bodies 18 in component "04_front_GROUND_BAR_290mm_FLAT_PSU"
ref_plane "工作平面6" through (0, 0, 0) normal (0, 0, 1) x (1, 0, 0) in component "04_rear_GROUND_BAR_290mm_FLAT_PSU"
sketch "草图6 (20)" plane through (0, 0, 0) normal (0, 0, 1) x (1, 0, 0) in component "04_rear_GROUND_BAR_290mm_FLAT_PSU"
  line L0 (20.45, 193.92) -> (28.45, 193.92)
  line L1 (28.45, 193.92) -> (28.45, 213.92)
  line L2 (28.45, 213.92) -> (20.45, 213.92)
  line L3 (20.45, 213.92) -> (20.45, 193.92)
extrude "PCI bottom lap end seat'" add sketch "草图6 (20)" along normal blind 3.2 bodies 19 in component "04_rear_GROUND_BAR_290mm_FLAT_PSU"
ref_plane "工作平面7" through (0, 0, 0) normal (0, 0, 1) x (1, 0, 0) in component "04_rear_GROUND_BAR_290mm_FLAT_PSU"
sketch "草图7 (18)" plane through (0, 0, 0) normal (0, 0, 1) x (1, 0, 0) in component "04_rear_GROUND_BAR_290mm_FLAT_PSU"
  line L0 (286.45, 193.92) -> (294.45, 193.92)
  line L1 (294.45, 193.92) -> (294.45, 213.92)
  line L2 (294.45, 213.92) -> (286.45, 213.92)
  line L3 (286.45, 213.92) -> (286.45, 193.92)
extrude "CPU bottom lap end seat'" add sketch "草图7 (18)" along normal blind 3.2 bodies 19 in component "04_rear_GROUND_BAR_290mm_FLAT_PSU"
ref_plane "工作平面13" through (0, 0, -0.01) normal (0, 0, 1) x (1, 0, 0) in component "16_PCI_INSET_SIDE_16_45mm"
sketch "草图13 (8)" plane through (0, 0, -0.01) normal (0, 0, 1) x (1, 0, 0) in component "16_PCI_INSET_SIDE_16_45mm"
  line L0 (20.3, 193.77) -> (28.6, 193.77)
  line L1 (28.6, 193.77) -> (28.6, 214.07)
  line L2 (28.6, 214.07) -> (20.3, 214.07)
  line L3 (20.3, 214.07) -> (20.3, 193.77)
extrude "Ground bar seat with lateral print clearance (1)" cut sketch "草图13 (8)" along normal blind 3.21 bodies 30 in component "16_PCI_INSET_SIDE_16_45mm"
ref_plane "工作平面8" through (0, 0, 0) normal (0, 0, 1) x (1, 0, 0) in component "04_rear_GROUND_BAR_290mm_FLAT_PSU"
sketch "草图8 (18)" plane through (0, 0, 0) normal (0, 0, 1) x (1, 0, 0) in component "04_rear_GROUND_BAR_290mm_FLAT_PSU"
  circle A0 centre (24.45, 203.92) radius 1.7
extrude "Bottom lap M3x6 clearance'" cut sketch "草图8 (18)" along normal blind 3.21 bodies 19 in component "04_rear_GROUND_BAR_290mm_FLAT_PSU"
ref_plane "工作平面14" through (0, 0, 3.2) normal (0, 0, 1) x (1, 0, 0) in component "16_PCI_INSET_SIDE_16_45mm"
sketch "草图14 (7)" plane through (0, 0, 3.2) normal (0, 0, 1) x (1, 0, 0) in component "16_PCI_INSET_SIDE_16_45mm"
  circle A0 centre (24.45, 203.92) radius 2.35
extrude "Bottom entry H4.5 insert for floor tie (1)" cut sketch "草图14 (7)" along normal blind 6.5 bodies 30 in component "16_PCI_INSET_SIDE_16_45mm"
ref_plane "工作平面11" through (0, 0, -0.01) normal (0, 0, 1) x (1, 0, 0) in component "16_CPU_VERTICAL_SIDE_FLUSH_TO_BEAM"
sketch "草图11 (12)" plane through (0, 0, -0.01) normal (0, 0, 1) x (1, 0, 0) in component "16_CPU_VERTICAL_SIDE_FLUSH_TO_BEAM"
  line L0 (286.3, 193.77) -> (294.6, 193.77)
  line L1 (294.6, 193.77) -> (294.6, 214.07)
  line L2 (294.6, 214.07) -> (286.3, 214.07)
  line L3 (286.3, 214.07) -> (286.3, 193.77)
extrude "Ground bar seat with lateral print clearance (1)'" cut sketch "草图11 (12)" along normal blind 3.21 bodies 29 in component "16_CPU_VERTICAL_SIDE_FLUSH_TO_BEAM"
ref_plane "工作平面9" through (0, 0, 0) normal (0, 0, 1) x (1, 0, 0) in component "04_rear_GROUND_BAR_290mm_FLAT_PSU"
sketch "草图9 (18)" plane through (0, 0, 0) normal (0, 0, 1) x (1, 0, 0) in component "04_rear_GROUND_BAR_290mm_FLAT_PSU"
  circle A0 centre (290.45, 203.92) radius 1.7
extrude "Bottom lap M3x6 clearance (1)'" cut sketch "草图9 (18)" along normal blind 3.21 bodies 19 in component "04_rear_GROUND_BAR_290mm_FLAT_PSU"
ref_plane "工作平面12" through (0, 0, 3.2) normal (0, 0, 1) x (1, 0, 0) in component "16_CPU_VERTICAL_SIDE_FLUSH_TO_BEAM"
sketch "草图12 (9)" plane through (0, 0, 3.2) normal (0, 0, 1) x (1, 0, 0) in component "16_CPU_VERTICAL_SIDE_FLUSH_TO_BEAM"
  circle A0 centre (290.45, 203.92) radius 2.35
extrude "Bottom entry H4.5 insert for floor tie (1)'" cut sketch "草图12 (9)" along normal blind 6.5 bodies 29 in component "16_CPU_VERTICAL_SIDE_FLUSH_TO_BEAM"
ref_plane "工作平面21" through (0, 0, 8) normal (0, 0, 1) x (1, 0, 0) in component "05_CENTERED_FLAT_PSU_CRADLE_OPEN_INTAKE"
sketch "草图21 (2)" plane through (0, 0, 8) normal (0, 0, 1) x (1, 0, 0) in component "05_CENTERED_FLAT_PSU_CRADLE_OPEN_INTAKE"
  circle A0 centre (79.4, 203.92) radius 1.7
extrude "Cradle to crossbar screw clearance (2)" cut sketch "草图21 (2)" along normal blind 22.01 bodies 20 in component "05_CENTERED_FLAT_PSU_CRADLE_OPEN_INTAKE"
ref_plane "工作平面22" through (0, 0, 11) normal (0, 0, 1) x (1, 0, 0) in component "05_CENTERED_FLAT_PSU_CRADLE_OPEN_INTAKE"
sketch "草图22 (2)" plane through (0, 0, 11) normal (0, 0, 1) x (1, 0, 0) in component "05_CENTERED_FLAT_PSU_CRADLE_OPEN_INTAKE"
  circle A0 centre (79.4, 203.92) radius 3.3
extrude "Cradle screw well leaving 3 mm web (2)" cut sketch "草图22 (2)" along normal blind 19.01 bodies 20 in component "05_CENTERED_FLAT_PSU_CRADLE_OPEN_INTAKE"
ref_plane "工作平面10" through (0, 0, 1.5) normal (0, 0, 1) x (1, 0, 0) in component "04_rear_GROUND_BAR_290mm_FLAT_PSU"
sketch "草图10 (15)" plane through (0, 0, 1.5) normal (0, 0, 1) x (1, 0, 0) in component "04_rear_GROUND_BAR_290mm_FLAT_PSU"
  circle A0 centre (79.4, 203.92) radius 2.35
extrude "Top entry H4.5 insert for cradle foot'" cut sketch "草图10 (15)" along normal blind 6.51 bodies 19 in component "04_rear_GROUND_BAR_290mm_FLAT_PSU"
ref_plane "工作平面23" through (0, 0, 8) normal (0, 0, 1) x (1, 0, 0) in component "05_CENTERED_FLAT_PSU_CRADLE_OPEN_INTAKE"
sketch "草图23 (2)" plane through (0, 0, 8) normal (0, 0, 1) x (1, 0, 0) in component "05_CENTERED_FLAT_PSU_CRADLE_OPEN_INTAKE"
  circle A0 centre (225.4, 203.92) radius 1.7
extrude "Cradle to crossbar screw clearance (3)" cut sketch "草图23 (2)" along normal blind 22.01 bodies 20 in component "05_CENTERED_FLAT_PSU_CRADLE_OPEN_INTAKE"
ref_plane "工作平面24" through (0, 0, 11) normal (0, 0, 1) x (1, 0, 0) in component "05_CENTERED_FLAT_PSU_CRADLE_OPEN_INTAKE"
sketch "草图24 (2)" plane through (0, 0, 11) normal (0, 0, 1) x (1, 0, 0) in component "05_CENTERED_FLAT_PSU_CRADLE_OPEN_INTAKE"
  circle A0 centre (225.4, 203.92) radius 3.3
extrude "Cradle screw well leaving 3 mm web (3)" cut sketch "草图24 (2)" along normal blind 19.01 bodies 20 in component "05_CENTERED_FLAT_PSU_CRADLE_OPEN_INTAKE"
ref_plane "工作平面11" through (0, 0, 1.5) normal (0, 0, 1) x (1, 0, 0) in component "04_rear_GROUND_BAR_290mm_FLAT_PSU"
sketch "草图11 (13)" plane through (0, 0, 1.5) normal (0, 0, 1) x (1, 0, 0) in component "04_rear_GROUND_BAR_290mm_FLAT_PSU"
  circle A0 centre (225.4, 203.92) radius 2.35
extrude "Top entry H4.5 insert for cradle foot (1)'" cut sketch "草图11 (13)" along normal blind 6.51 bodies 19 in component "04_rear_GROUND_BAR_290mm_FLAT_PSU"
ref_plane "工作平面25" through (0, 0, 23.99) normal (0, 0, 1) x (1, 0, 0) in component "05_CENTERED_FLAT_PSU_CRADLE_OPEN_INTAKE"
sketch "草图25 (2)" plane through (0, 0, 23.99) normal (0, 0, 1) x (1, 0, 0) in component "05_CENTERED_FLAT_PSU_CRADLE_OPEN_INTAKE"
  line L0 (87.1, 35) -> (90.7, 35)
  line L1 (90.7, 35) -> (90.7, 37.4)
  line L2 (90.7, 37.4) -> (87.1, 37.4)
  line L3 (87.1, 37.4) -> (87.1, 35)
extrude "3 mm strap slot outside PSU fan intake" cut sketch "草图25 (2)" along normal blind 6.02 bodies 20 in component "05_CENTERED_FLAT_PSU_CRADLE_OPEN_INTAKE"
ref_plane "工作平面26" through (0, 0, 23.99) normal (0, 0, 1) x (1, 0, 0) in component "05_CENTERED_FLAT_PSU_CRADLE_OPEN_INTAKE"
sketch "草图26 (2)" plane through (0, 0, 23.99) normal (0, 0, 1) x (1, 0, 0) in component "05_CENTERED_FLAT_PSU_CRADLE_OPEN_INTAKE"
  line L0 (87.1, 206.2) -> (90.7, 206.2)
  line L1 (90.7, 206.2) -> (90.7, 208.6)
  line L2 (90.7, 208.6) -> (87.1, 208.6)
  line L3 (87.1, 208.6) -> (87.1, 206.2)
extrude "3 mm strap slot outside PSU fan intake (1)" cut sketch "草图26 (2)" along normal blind 6.02 bodies 20 in component "05_CENTERED_FLAT_PSU_CRADLE_OPEN_INTAKE"
ref_plane "工作平面27" through (0, 0, 23.99) normal (0, 0, 1) x (1, 0, 0) in component "05_CENTERED_FLAT_PSU_CRADLE_OPEN_INTAKE"
sketch "草图27 (2)" plane through (0, 0, 23.99) normal (0, 0, 1) x (1, 0, 0) in component "05_CENTERED_FLAT_PSU_CRADLE_OPEN_INTAKE"
  line L0 (214.1, 35) -> (217.7, 35)
  line L1 (217.7, 35) -> (217.7, 37.4)
  line L2 (217.7, 37.4) -> (214.1, 37.4)
  line L3 (214.1, 37.4) -> (214.1, 35)
extrude "3 mm strap slot outside PSU fan intake (2)" cut sketch "草图27 (2)" along normal blind 6.02 bodies 20 in component "05_CENTERED_FLAT_PSU_CRADLE_OPEN_INTAKE"
ref_plane "工作平面28" through (0, 0, 23.99) normal (0, 0, 1) x (1, 0, 0) in component "05_CENTERED_FLAT_PSU_CRADLE_OPEN_INTAKE"
sketch "草图28 (2)" plane through (0, 0, 23.99) normal (0, 0, 1) x (1, 0, 0) in component "05_CENTERED_FLAT_PSU_CRADLE_OPEN_INTAKE"
  line L0 (214.1, 206.2) -> (217.7, 206.2)
  line L1 (217.7, 206.2) -> (217.7, 208.6)
  line L2 (217.7, 208.6) -> (214.1, 208.6)
  line L3 (214.1, 208.6) -> (214.1, 206.2)
extrude "3 mm strap slot outside PSU fan intake (3)" cut sketch "草图28 (2)" along normal blind 6.02 bodies 20 in component "05_CENTERED_FLAT_PSU_CRADLE_OPEN_INTAKE"
ref_plane "工作平面7" through (0, 0, 210) normal (0, 0, 1) x (1, 0, 0) in component "10_GPU_140_FAN_MOUNT"
sketch "草图7 (19)" plane through (0, 0, 210) normal (0, 0, 1) x (1, 0, 0) in component "10_GPU_140_FAN_MOUNT"
  line L0 (26.4, -19) -> (38.4, -19)
  line L1 (38.4, -19) -> (38.4, -9)
  line L2 (38.4, -9) -> (26.4, -9)
  line L3 (26.4, -9) -> (26.4, -19)
extrude "Integral 3 mm fan panel fastening tab" add sketch "草图7 (19)" along normal blind 3 bodies 1 in component "10_GPU_140_FAN_MOUNT"
ref_plane "工作平面8" through (0, 0, 210) normal (0, 0, 1) x (1, 0, 0) in component "10_GPU_140_FAN_MOUNT"
sketch "草图8 (19)" plane through (0, 0, 210) normal (0, 0, 1) x (1, 0, 0) in component "10_GPU_140_FAN_MOUNT"
  circle A0 centre (32.4, -14) radius 1.7
extrude "M3x6 fan panel tab clearance" cut sketch "草图8 (19)" along normal blind 3.01 bodies 1 in component "10_GPU_140_FAN_MOUNT"
ref_plane "工作平面14" through (0, 0, 148) normal (0, 0, 1) x (1, 0, 0) in component "20_ONE_PIECE_DUAL_140_FAN_RAIL_284mm"
sketch "草图14 (8)" plane through (0, 0, 148) normal (0, 0, 1) x (1, 0, 0) in component "20_ONE_PIECE_DUAL_140_FAN_RAIL_284mm"
  line L0 (26.4, -19) -> (38.4, -19)
  line L1 (38.4, -19) -> (38.4, -9)
  line L2 (38.4, -9) -> (26.4, -9)
  line L3 (26.4, -9) -> (26.4, -19)
extrude "Integral fan panel tab support pad" add sketch "草图14 (8)" along normal blind 12 bodies 35 in component "20_ONE_PIECE_DUAL_140_FAN_RAIL_284mm"
ref_plane "工作平面15" through (0, 0, 153.5) normal (0, 0, 1) x (1, 0, 0) in component "20_ONE_PIECE_DUAL_140_FAN_RAIL_284mm"
sketch "草图15 (6)" plane through (0, 0, 153.5) normal (0, 0, 1) x (1, 0, 0) in component "20_ONE_PIECE_DUAL_140_FAN_RAIL_284mm"
  circle A0 centre (32.4, -14) radius 2.35
extrude "H4.5 insert for fan panel M3x6 fastening" cut sketch "草图15 (6)" along normal blind 6.51 bodies 35 in component "20_ONE_PIECE_DUAL_140_FAN_RAIL_284mm"
ref_plane "工作平面9" through (0, 0, 210) normal (0, 0, 1) x (1, 0, 0) in component "10_GPU_140_FAN_MOUNT"
sketch "草图9 (19)" plane through (0, 0, 210) normal (0, 0, 1) x (1, 0, 0) in component "10_GPU_140_FAN_MOUNT"
  line L0 (126.4, -19) -> (138.4, -19)
  line L1 (138.4, -19) -> (138.4, -9)
  line L2 (138.4, -9) -> (126.4, -9)
  line L3 (126.4, -9) -> (126.4, -19)
extrude "Integral 3 mm fan panel fastening tab (1)" add sketch "草图9 (19)" along normal blind 3 bodies 1 in component "10_GPU_140_FAN_MOUNT"
ref_plane "工作平面10" through (0, 0, 210) normal (0, 0, 1) x (1, 0, 0) in component "10_GPU_140_FAN_MOUNT"
sketch "草图10 (16)" plane through (0, 0, 210) normal (0, 0, 1) x (1, 0, 0) in component "10_GPU_140_FAN_MOUNT"
  circle A0 centre (132.4, -14) radius 1.7
extrude "M3x6 fan panel tab clearance (1)" cut sketch "草图10 (16)" along normal blind 3.01 bodies 1 in component "10_GPU_140_FAN_MOUNT"
ref_plane "工作平面16" through (0, 0, 148) normal (0, 0, 1) x (1, 0, 0) in component "20_ONE_PIECE_DUAL_140_FAN_RAIL_284mm"
sketch "草图16 (5)" plane through (0, 0, 148) normal (0, 0, 1) x (1, 0, 0) in component "20_ONE_PIECE_DUAL_140_FAN_RAIL_284mm"
  line L0 (126.4, -19) -> (138.4, -19)
  line L1 (138.4, -19) -> (138.4, -9)
  line L2 (138.4, -9) -> (126.4, -9)
  line L3 (126.4, -9) -> (126.4, -19)
extrude "Integral fan panel tab support pad (1)" add sketch "草图16 (5)" along normal blind 12 bodies 35 in component "20_ONE_PIECE_DUAL_140_FAN_RAIL_284mm"
ref_plane "工作平面17" through (0, 0, 153.5) normal (0, 0, 1) x (1, 0, 0) in component "20_ONE_PIECE_DUAL_140_FAN_RAIL_284mm"
sketch "草图17 (3)" plane through (0, 0, 153.5) normal (0, 0, 1) x (1, 0, 0) in component "20_ONE_PIECE_DUAL_140_FAN_RAIL_284mm"
  circle A0 centre (132.4, -14) radius 2.35
extrude "H4.5 insert for fan panel M3x6 fastening (1)" cut sketch "草图17 (3)" along normal blind 6.51 bodies 35 in component "20_ONE_PIECE_DUAL_140_FAN_RAIL_284mm"
ref_plane "工作平面7" through (0, 0, 210) normal (0, 0, 1) x (1, 0, 0) in component "10_CPU_140_FAN_MOUNT"